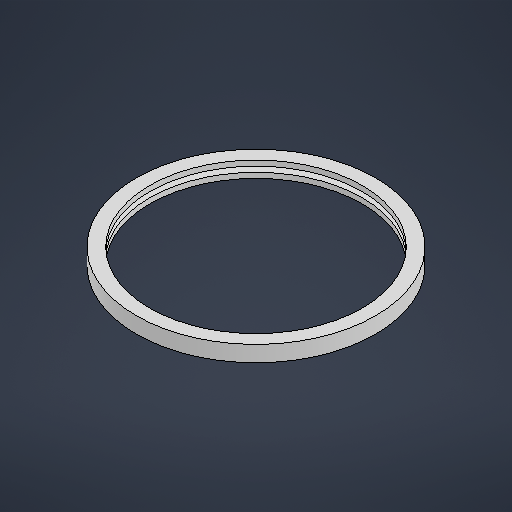
# Autodesk Inventor part: SealIn
Saved by Autodesk Inventor 2027.2 (Build 312334000, 334)
## iProperties
Created: 2026-11-16
Part Number: SealIn
Material: Generic
Document SubType Name: Modeling
Designer: Gasteng5
Density: 1 g/cm^3
Appearance: Default
Mass: 6.26573 g
Surface Area: 76.62 cm^2
Volume: 6.26573 cm^3
Author: Gasteng5
Autodesk Inventor part; units mm, degrees
ref_plane "YZ Plane" through (0, 0, 0) normal (1, 0, 0) x (0, 1, 0)
ref_plane "XZ Plane" through (0, 0, 0) normal (0, 1, 0) x (-1, 0, 0)
ref_plane "XY Plane" through (0, 0, 0) normal (0, 0, 1) x (1, 0, 0)
sketch "Sketch1" plane through (0, 0, 0) normal (1, 0, 0) x (0, 1, 0)
  line L0 (0, 0) -> (-42.5, 0) construction
  line L1 (-45, -3) -> (-40, -3)
  line L2 (-40, 3) -> (-45, 3)
  line L3 (-45, 3) -> (-45, -3)
  line L4 (-45, -3) -> (-40, 3) construction
  line L5 (-40, -3) -> (-45, 3) construction
  line L6 (-40, -3) -> (-40, -1)
  line L7 (-40, -1) -> (-43.3333, -1)
  line L8 (-43.3333, 0) -> (-43.3333, -1)
  line L9 (-45, 0) -> (-40, 0)
  line L10 (-40, 1) -> (-43.3333, 1)
  line L11 (-43.3333, 0) -> (-43.3333, 1)
  line L12 (-40, 3) -> (-40, 1)
  line L13 (0, -4.2) -> (0, 4.2) projected
  dimension "d7" = 2
  dimension "d8" = 40
  dimension "d11" = 45
  dimension "d12" = 2
  constraints: 26 end point, 3 midpoint, 3 parallel, 3 point on line, 2 horizontal, 2 symmetric about line, 2 vertical, 1 coincident, 1 perpendicular
  measures "d7" distance of L1.end L6.end
  measures "d8" distance from line of L0.start L6
  measures "d11" distance from line of L0.start L3
  measures "d12" distance between parallel lines of L7 L10
revolve "Revolution1" add sketch "Sketch1" angle 360 about axis through (0, 0, -10) along (0, 0, 1)
equation "\"d8\" = 0.5 * BinnenDiaMeter"
equation "\"d11\" = 0.5 * BuitenDiaMeter"
equation "\"Thickness\" = 2"
equation "\"BinnenDiaMeter\" = 80"
equation "\"BuitenDiaMeter\" = 90"
body "Solid1"
